Autodesk Fusion 360 part; units mm, degrees
(part 6 of 28)
  line L3353 (47.3065, 73.2735, -1.4859) -> (47.3065, 76.4735, -1.4859)
  line L3354 (47.3065, 76.4735, -1.4859) -> (49.3065, 76.4735, -1.4859)
  line L3355 (49.3065, 76.4735, -1.4859) -> (49.3065, 73.2735, -1.4859)
  line L3356 (84.2315, 73.2735, -1.4859) -> (82.2315, 73.2735, -1.4859)
  line L3357 (82.2315, 73.2735, -1.4859) -> (82.2315, 76.4735, -1.4859)
  line L3358 (82.2315, 76.4735, -1.4859) -> (84.2315, 76.4735, -1.4859)
  line L3359 (84.2315, 76.4735, -1.4859) -> (84.2315, 73.2735, -1.4859)
  line L3360 (119.1565, 73.2735, -1.4859) -> (117.1565, 73.2735, -1.4859)
  line L3361 (117.1565, 73.2735, -1.4859) -> (117.1565, 76.4735, -1.4859)
  line L3362 (117.1565, 76.4735, -1.4859) -> (119.1565, 76.4735, -1.4859)
  line L3363 (119.1565, 76.4735, -1.4859) -> (119.1565, 73.2735, -1.4859)
  line L3364 (19.1718, 76.4304, -1.4859) -> (19.3529, 76.3554, -1.4859)
  line L3365 (19.3529, 76.3554, -1.4859) -> (19.5159, 76.2465, -1.4859)
  line L3366 (19.5159, 76.2465, -1.4859) -> (19.6545, 76.1079, -1.4859)
  line L3367 (19.6545, 76.1079, -1.4859) -> (19.7634, 75.9449, -1.4859)
  line L3368 (19.7634, 75.9449, -1.4859) -> (19.8385, 75.7638, -1.4859)
  line L3369 (19.8385, 75.7638, -1.4859) -> (19.8767, 75.5715, -1.4859)
  line L3370 (19.8767, 75.5715, -1.4859) -> (19.8815, 75.4735, -1.4859)
  line L3371 (19.8815, 75.4735, -1.4859) -> (19.8815, 74.2735, -1.4859)
  line L3372 (19.8815, 74.2735, -1.4859) -> (19.8767, 74.1755, -1.4859)
  line L3373 (19.8767, 74.1755, -1.4859) -> (19.8385, 73.9832, -1.4859)
  line L3374 (19.8385, 73.9832, -1.4859) -> (19.7634, 73.8021, -1.4859)
  line L3375 (19.7634, 73.8021, -1.4859) -> (19.6545, 73.6391, -1.4859)
  line L3376 (19.6545, 73.6391, -1.4859) -> (19.5159, 73.5005, -1.4859)
  line L3377 (19.5159, 73.5005, -1.4859) -> (19.3529, 73.3916, -1.4859)
  line L3378 (19.3529, 73.3916, -1.4859) -> (19.1718, 73.3165, -1.4859)
  line L3379 (19.1718, 73.3165, -1.4859) -> (18.9795, 73.2783, -1.4859)
  line L3380 (18.9795, 73.2783, -1.4859) -> (18.7835, 73.2783, -1.4859)
  line L3381 (18.7835, 73.2783, -1.4859) -> (18.5912, 73.3165, -1.4859)
  line L3382 (18.5912, 73.3165, -1.4859) -> (18.4101, 73.3916, -1.4859)
  line L3383 (18.4101, 73.3916, -1.4859) -> (18.2471, 73.5005, -1.4859)
  line L3384 (18.2471, 73.5005, -1.4859) -> (18.1085, 73.6391, -1.4859)
  line L3385 (18.1085, 73.6391, -1.4859) -> (17.9996, 73.8021, -1.4859)
  line L3386 (17.9996, 73.8021, -1.4859) -> (17.9246, 73.9832, -1.4859)
  line L3387 (17.9246, 73.9832, -1.4859) -> (17.8863, 74.1755, -1.4859)
  line L3388 (17.8863, 74.1755, -1.4859) -> (17.8815, 74.2735, -1.4859)
  line L3389 (17.8815, 74.2735, -1.4859) -> (17.8815, 75.4735, -1.4859)
  line L3390 (17.8815, 75.4735, -1.4859) -> (17.8863, 75.5715, -1.4859)
  line L3391 (17.8863, 75.5715, -1.4859) -> (17.9246, 75.7638, -1.4859)
  line L3392 (17.9246, 75.7638, -1.4859) -> (17.9996, 75.9449, -1.4859)
  line L3393 (17.9996, 75.9449, -1.4859) -> (18.1085, 76.1079, -1.4859)
  line L3394 (18.1085, 76.1079, -1.4859) -> (18.2471, 76.2465, -1.4859)
  line L3395 (18.2471, 76.2465, -1.4859) -> (18.4101, 76.3554, -1.4859)
  line L3396 (18.4101, 76.3554, -1.4859) -> (18.5912, 76.4304, -1.4859)
  line L3397 (18.5912, 76.4304, -1.4859) -> (18.7835, 76.4687, -1.4859)
  line L3398 (18.7835, 76.4687, -1.4859) -> (18.9795, 76.4687, -1.4859)
  line L3399 (18.9795, 76.4687, -1.4859) -> (19.1718, 76.4304, -1.4859)
  line L3400 (54.0968, 76.4304, -1.4859) -> (54.2779, 76.3554, -1.4859)
  line L3401 (54.2779, 76.3554, -1.4859) -> (54.4409, 76.2465, -1.4859)
  line L3402 (54.4409, 76.2465, -1.4859) -> (54.5795, 76.1079, -1.4859)
  line L3403 (54.5795, 76.1079, -1.4859) -> (54.6884, 75.9449, -1.4859)
  line L3404 (54.6884, 75.9449, -1.4859) -> (54.7635, 75.7638, -1.4859)
  line L3405 (54.7635, 75.7638, -1.4859) -> (54.8017, 75.5715, -1.4859)
  line L3406 (54.8017, 75.5715, -1.4859) -> (54.8065, 75.4735, -1.4859)
  line L3407 (54.8065, 75.4735, -1.4859) -> (54.8065, 74.2735, -1.4859)
  line L3408 (54.8065, 74.2735, -1.4859) -> (54.8017, 74.1755, -1.4859)
  line L3409 (54.8017, 74.1755, -1.4859) -> (54.7635, 73.9832, -1.4859)
  line L3410 (54.7635, 73.9832, -1.4859) -> (54.6884, 73.8021, -1.4859)
  line L3411 (54.6884, 73.8021, -1.4859) -> (54.5795, 73.6391, -1.4859)
  line L3412 (54.5795, 73.6391, -1.4859) -> (54.4409, 73.5005, -1.4859)
  line L3413 (54.4409, 73.5005, -1.4859) -> (54.2779, 73.3916, -1.4859)
  line L3414 (54.2779, 73.3916, -1.4859) -> (54.0968, 73.3165, -1.4859)
  line L3415 (54.0968, 73.3165, -1.4859) -> (53.9045, 73.2783, -1.4859)
  line L3416 (53.9045, 73.2783, -1.4859) -> (53.7085, 73.2783, -1.4859)
  line L3417 (53.7085, 73.2783, -1.4859) -> (53.5162, 73.3165, -1.4859)
  line L3418 (53.5162, 73.3165, -1.4859) -> (53.3351, 73.3916, -1.4859)
  line L3419 (53.3351, 73.3916, -1.4859) -> (53.1721, 73.5005, -1.4859)
  line L3420 (53.1721, 73.5005, -1.4859) -> (53.0335, 73.6391, -1.4859)
  line L3421 (53.0335, 73.6391, -1.4859) -> (52.9246, 73.8021, -1.4859)
  line L3422 (52.9246, 73.8021, -1.4859) -> (52.8496, 73.9832, -1.4859)
  line L3423 (52.8496, 73.9832, -1.4859) -> (52.8113, 74.1755, -1.4859)
  line L3424 (52.8113, 74.1755, -1.4859) -> (52.8065, 74.2735, -1.4859)
  line L3425 (52.8065, 74.2735, -1.4859) -> (52.8065, 75.4735, -1.4859)
  line L3426 (52.8065, 75.4735, -1.4859) -> (52.8113, 75.5715, -1.4859)
  line L3427 (52.8113, 75.5715, -1.4859) -> (52.8496, 75.7638, -1.4859)
  line L3428 (52.8496, 75.7638, -1.4859) -> (52.9246, 75.9449, -1.4859)
  line L3429 (52.9246, 75.9449, -1.4859) -> (53.0335, 76.1079, -1.4859)
  line L3430 (53.0335, 76.1079, -1.4859) -> (53.1721, 76.2465, -1.4859)
  line L3431 (53.1721, 76.2465, -1.4859) -> (53.3351, 76.3554, -1.4859)
  line L3432 (53.3351, 76.3554, -1.4859) -> (53.5162, 76.4304, -1.4859)
  line L3433 (53.5162, 76.4304, -1.4859) -> (53.7085, 76.4687, -1.4859)
  line L3434 (53.7085, 76.4687, -1.4859) -> (53.9045, 76.4687, -1.4859)
  line L3435 (53.9045, 76.4687, -1.4859) -> (54.0968, 76.4304, -1.4859)
  line L3436 (89.0218, 76.4304, -1.4859) -> (89.2029, 76.3554, -1.4859)
  line L3437 (89.2029, 76.3554, -1.4859) -> (89.3659, 76.2465, -1.4859)
  line L3438 (89.3659, 76.2465, -1.4859) -> (89.5045, 76.1079, -1.4859)
  line L3439 (89.5045, 76.1079, -1.4859) -> (89.6134, 75.9449, -1.4859)
  line L3440 (89.6134, 75.9449, -1.4859) -> (89.6885, 75.7638, -1.4859)
  line L3441 (89.6885, 75.7638, -1.4859) -> (89.7267, 75.5715, -1.4859)
  line L3442 (89.7267, 75.5715, -1.4859) -> (89.7315, 75.4735, -1.4859)
  line L3443 (89.7315, 75.4735, -1.4859) -> (89.7315, 74.2735, -1.4859)
  line L3444 (89.7315, 74.2735, -1.4859) -> (89.7267, 74.1755, -1.4859)
  line L3445 (89.7267, 74.1755, -1.4859) -> (89.6885, 73.9832, -1.4859)
  line L3446 (89.6885, 73.9832, -1.4859) -> (89.6134, 73.8021, -1.4859)
  line L3447 (89.6134, 73.8021, -1.4859) -> (89.5045, 73.6391, -1.4859)
  line L3448 (89.5045, 73.6391, -1.4859) -> (89.3659, 73.5005, -1.4859)
  line L3449 (89.3659, 73.5005, -1.4859) -> (89.2029, 73.3916, -1.4859)
  line L3450 (89.2029, 73.3916, -1.4859) -> (89.0218, 73.3165, -1.4859)
  line L3451 (89.0218, 73.3165, -1.4859) -> (88.8295, 73.2783, -1.4859)
  line L3452 (88.8295, 73.2783, -1.4859) -> (88.6335, 73.2783, -1.4859)
  line L3453 (88.6335, 73.2783, -1.4859) -> (88.4412, 73.3165, -1.4859)
  line L3454 (88.4412, 73.3165, -1.4859) -> (88.2601, 73.3916, -1.4859)
  line L3455 (88.2601, 73.3916, -1.4859) -> (88.0971, 73.5005, -1.4859)
  line L3456 (88.0971, 73.5005, -1.4859) -> (87.9585, 73.6391, -1.4859)
  line L3457 (87.9585, 73.6391, -1.4859) -> (87.8496, 73.8021, -1.4859)
  line L3458 (87.8496, 73.8021, -1.4859) -> (87.7746, 73.9832, -1.4859)
  line L3459 (87.7746, 73.9832, -1.4859) -> (87.7363, 74.1755, -1.4859)
  line L3460 (87.7363, 74.1755, -1.4859) -> (87.7315, 74.2735, -1.4859)
  line L3461 (87.7315, 74.2735, -1.4859) -> (87.7315, 75.4735, -1.4859)
  line L3462 (87.7315, 75.4735, -1.4859) -> (87.7363, 75.5715, -1.4859)
  line L3463 (87.7363, 75.5715, -1.4859) -> (87.7746, 75.7638, -1.4859)
  line L3464 (87.7746, 75.7638, -1.4859) -> (87.8496, 75.9449, -1.4859)
  line L3465 (87.8496, 75.9449, -1.4859) -> (87.9585, 76.1079, -1.4859)
  line L3466 (87.9585, 76.1079, -1.4859) -> (88.0971, 76.2465, -1.4859)
  line L3467 (88.0971, 76.2465, -1.4859) -> (88.2601, 76.3554, -1.4859)
  line L3468 (88.2601, 76.3554, -1.4859) -> (88.4412, 76.4304, -1.4859)
  line L3469 (88.4412, 76.4304, -1.4859) -> (88.6335, 76.4687, -1.4859)
  line L3470 (88.6335, 76.4687, -1.4859) -> (88.8295, 76.4687, -1.4859)
  line L3471 (88.8295, 76.4687, -1.4859) -> (89.0218, 76.4304, -1.4859)
  line L3472 (123.9468, 76.4304, -1.4859) -> (124.1279, 76.3554, -1.4859)
  line L3473 (124.1279, 76.3554, -1.4859) -> (124.2909, 76.2465, -1.4859)
  line L3474 (124.2909, 76.2465, -1.4859) -> (124.4295, 76.1079, -1.4859)
  line L3475 (124.4295, 76.1079, -1.4859) -> (124.5384, 75.9449, -1.4859)
  line L3476 (124.5384, 75.9449, -1.4859) -> (124.6135, 75.7638, -1.4859)
  line L3477 (124.6135, 75.7638, -1.4859) -> (124.6517, 75.5715, -1.4859)
  line L3478 (124.6517, 75.5715, -1.4859) -> (124.6565, 75.4735, -1.4859)
  line L3479 (124.6565, 75.4735, -1.4859) -> (124.6565, 74.2735, -1.4859)
  line L3480 (124.6565, 74.2735, -1.4859) -> (124.6517, 74.1755, -1.4859)
  line L3481 (124.6517, 74.1755, -1.4859) -> (124.6135, 73.9832, -1.4859)
  line L3482 (124.6135, 73.9832, -1.4859) -> (124.5384, 73.8021, -1.4859)
  line L3483 (124.5384, 73.8021, -1.4859) -> (124.4295, 73.6391, -1.4859)
  line L3484 (124.4295, 73.6391, -1.4859) -> (124.2909, 73.5005, -1.4859)
  line L3485 (124.2909, 73.5005, -1.4859) -> (124.1279, 73.3916, -1.4859)
  line L3486 (124.1279, 73.3916, -1.4859) -> (123.9468, 73.3165, -1.4859)
  line L3487 (123.9468, 73.3165, -1.4859) -> (123.7545, 73.2783, -1.4859)
  line L3488 (123.7545, 73.2783, -1.4859) -> (123.5585, 73.2783, -1.4859)
  line L3489 (123.5585, 73.2783, -1.4859) -> (123.3662, 73.3165, -1.4859)
  line L3490 (123.3662, 73.3165, -1.4859) -> (123.1851, 73.3916, -1.4859)
  line L3491 (123.1851, 73.3916, -1.4859) -> (123.0221, 73.5005, -1.4859)
  line L3492 (123.0221, 73.5005, -1.4859) -> (122.8835, 73.6391, -1.4859)
  line L3493 (122.8835, 73.6391, -1.4859) -> (122.7746, 73.8021, -1.4859)
  line L3494 (122.7746, 73.8021, -1.4859) -> (122.6996, 73.9832, -1.4859)
  line L3495 (122.6996, 73.9832, -1.4859) -> (122.6613, 74.1755, -1.4859)
  line L3496 (122.6613, 74.1755, -1.4859) -> (122.6565, 74.2735, -1.4859)
  line L3497 (122.6565, 74.2735, -1.4859) -> (122.6565, 75.4735, -1.4859)
  line L3498 (122.6565, 75.4735, -1.4859) -> (122.6613, 75.5715, -1.4859)
  line L3499 (122.6613, 75.5715, -1.4859) -> (122.6996, 75.7638, -1.4859)
  line L3500 (122.6996, 75.7638, -1.4859) -> (122.7746, 75.9449, -1.4859)
  line L3501 (122.7746, 75.9449, -1.4859) -> (122.8835, 76.1079, -1.4859)
  line L3502 (122.8835, 76.1079, -1.4859) -> (123.0221, 76.2465, -1.4859)
  line L3503 (123.0221, 76.2465, -1.4859) -> (123.1851, 76.3554, -1.4859)
  line L3504 (123.1851, 76.3554, -1.4859) -> (123.3662, 76.4304, -1.4859)
  line L3505 (123.3662, 76.4304, -1.4859) -> (123.5585, 76.4687, -1.4859)
  line L3506 (123.5585, 76.4687, -1.4859) -> (123.7545, 76.4687, -1.4859)
  line L3507 (123.7545, 76.4687, -1.4859) -> (123.9468, 76.4304, -1.4859)
  line L3508 (14.4673, 82.8132, -1.4859) -> (14.661, 82.7825, -1.4859)
  line L3509 (14.661, 82.7825, -1.4859) -> (14.8475, 82.7219, -1.4859)
  line L3510 (14.8475, 82.7219, -1.4859) -> (15.0223, 82.6328, -1.4859)
  line L3511 (15.0223, 82.6328, -1.4859) -> (15.181, 82.5175, -1.4859)
  line L3512 (15.181, 82.5175, -1.4859) -> (15.3197, 82.3788, -1.4859)
  line L3513 (15.3197, 82.3788, -1.4859) -> (15.435, 82.2202, -1.4859)
  line L3514 (15.435, 82.2202, -1.4859) -> (15.524, 82.0454, -1.4859)
  line L3515 (15.524, 82.0454, -1.4859) -> (15.5846, 81.8588, -1.4859)
  line L3516 (15.5846, 81.8588, -1.4859) -> (15.6153, 81.6651, -1.4859)
  line L3517 (15.6153, 81.6651, -1.4859) -> (15.6153, 81.469, -1.4859)
  line L3518 (15.6153, 81.469, -1.4859) -> (15.5846, 81.2752, -1.4859)
  line L3519 (15.5846, 81.2752, -1.4859) -> (15.524, 81.0887, -1.4859)
  line L3520 (15.524, 81.0887, -1.4859) -> (15.435, 80.9139, -1.4859)
  line L3521 (15.435, 80.9139, -1.4859) -> (15.3197, 80.7552, -1.4859)
  line L3522 (15.3197, 80.7552, -1.4859) -> (15.181, 80.6165, -1.4859)
  line L3523 (15.181, 80.6165, -1.4859) -> (15.0223, 80.5012, -1.4859)
  line L3524 (15.0223, 80.5012, -1.4859) -> (14.8475, 80.4122, -1.4859)
  line L3525 (14.8475, 80.4122, -1.4859) -> (14.661, 80.3516, -1.4859)
  line L3526 (14.661, 80.3516, -1.4859) -> (14.4673, 80.3209, -1.4859)
  line L3527 (14.4673, 80.3209, -1.4859) -> (14.3692, 80.317, -1.4859)
  line L3528 (14.3692, 80.317, -1.4859) -> (13.8692, 80.317, -1.4859)
  line L3529 (13.8692, 80.317, -1.4859) -> (13.7711, 80.3209, -1.4859)
  line L3530 (13.7711, 80.3209, -1.4859) -> (13.5774, 80.3516, -1.4859)
  line L3531 (13.5774, 80.3516, -1.4859) -> (13.3908, 80.4122, -1.4859)
  line L3532 (13.3908, 80.4122, -1.4859) -> (13.2161, 80.5012, -1.4859)
  line L3533 (13.2161, 80.5012, -1.4859) -> (13.0574, 80.6165, -1.4859)
  line L3534 (13.0574, 80.6165, -1.4859) -> (12.9187, 80.7552, -1.4859)
  line L3535 (12.9187, 80.7552, -1.4859) -> (12.8034, 80.9139, -1.4859)
  line L3536 (12.8034, 80.9139, -1.4859) -> (12.7143, 81.0887, -1.4859)
  line L3537 (12.7143, 81.0887, -1.4859) -> (12.6537, 81.2752, -1.4859)
  line L3538 (12.6537, 81.2752, -1.4859) -> (12.623, 81.469, -1.4859)
  line L3539 (12.623, 81.469, -1.4859) -> (12.623, 81.6651, -1.4859)
  line L3540 (12.623, 81.6651, -1.4859) -> (12.6537, 81.8588, -1.4859)
  line L3541 (12.6537, 81.8588, -1.4859) -> (12.7143, 82.0454, -1.4859)
  line L3542 (12.7143, 82.0454, -1.4859) -> (12.8034, 82.2202, -1.4859)
  line L3543 (12.8034, 82.2202, -1.4859) -> (12.9187, 82.3788, -1.4859)
  line L3544 (12.9187, 82.3788, -1.4859) -> (13.0574, 82.5175, -1.4859)
  line L3545 (13.0574, 82.5175, -1.4859) -> (13.2161, 82.6328, -1.4859)
  line L3546 (13.2161, 82.6328, -1.4859) -> (13.3908, 82.7219, -1.4859)
  line L3547 (13.3908, 82.7219, -1.4859) -> (13.5774, 82.7825, -1.4859)
  line L3548 (13.5774, 82.7825, -1.4859) -> (13.7711, 82.8132, -1.4859)
  line L3549 (13.7711, 82.8132, -1.4859) -> (13.8692, 82.817, -1.4859)
  line L3550 (13.8692, 82.817, -1.4859) -> (14.3692, 82.817, -1.4859)
  line L3551 (14.3692, 82.817, -1.4859) -> (14.4673, 82.8132, -1.4859)
  line L3552 (22.0873, 82.8132, -1.4859) -> (22.281, 82.7825, -1.4859)
  line L3553 (22.281, 82.7825, -1.4859) -> (22.4675, 82.7219, -1.4859)
  line L3554 (22.4675, 82.7219, -1.4859) -> (22.6423, 82.6328, -1.4859)
  line L3555 (22.6423, 82.6328, -1.4859) -> (22.801, 82.5175, -1.4859)
  line L3556 (22.801, 82.5175, -1.4859) -> (22.9397, 82.3788, -1.4859)
  line L3557 (22.9397, 82.3788, -1.4859) -> (23.055, 82.2202, -1.4859)
  line L3558 (23.055, 82.2202, -1.4859) -> (23.144, 82.0454, -1.4859)
  line L3559 (23.144, 82.0454, -1.4859) -> (23.2046, 81.8588, -1.4859)
  line L3560 (23.2046, 81.8588, -1.4859) -> (23.2353, 81.6651, -1.4859)
  line L3561 (23.2353, 81.6651, -1.4859) -> (23.2353, 81.469, -1.4859)
  line L3562 (23.2353, 81.469, -1.4859) -> (23.2046, 81.2752, -1.4859)
  line L3563 (23.2046, 81.2752, -1.4859) -> (23.144, 81.0887, -1.4859)
  line L3564 (23.144, 81.0887, -1.4859) -> (23.055, 80.9139, -1.4859)
  line L3565 (23.055, 80.9139, -1.4859) -> (22.9397, 80.7552, -1.4859)
  line L3566 (22.9397, 80.7552, -1.4859) -> (22.801, 80.6165, -1.4859)
  line L3567 (22.801, 80.6165, -1.4859) -> (22.6423, 80.5012, -1.4859)
  line L3568 (22.6423, 80.5012, -1.4859) -> (22.4675, 80.4122, -1.4859)
  line L3569 (22.4675, 80.4122, -1.4859) -> (22.281, 80.3516, -1.4859)
  line L3570 (22.281, 80.3516, -1.4859) -> (22.0873, 80.3209, -1.4859)
  line L3571 (22.0873, 80.3209, -1.4859) -> (21.9892, 80.317, -1.4859)
  line L3572 (21.9892, 80.317, -1.4859) -> (21.4892, 80.317, -1.4859)
  line L3573 (21.4892, 80.317, -1.4859) -> (21.3911, 80.3209, -1.4859)
  line L3574 (21.3911, 80.3209, -1.4859) -> (21.1974, 80.3516, -1.4859)
  line L3575 (21.1974, 80.3516, -1.4859) -> (21.0108, 80.4122, -1.4859)
  line L3576 (21.0108, 80.4122, -1.4859) -> (20.8361, 80.5012, -1.4859)
  line L3577 (20.8361, 80.5012, -1.4859) -> (20.6774, 80.6165, -1.4859)
  line L3578 (20.6774, 80.6165, -1.4859) -> (20.5387, 80.7552, -1.4859)
  line L3579 (20.5387, 80.7552, -1.4859) -> (20.4234, 80.9139, -1.4859)
  line L3580 (20.4234, 80.9139, -1.4859) -> (20.3343, 81.0887, -1.4859)
  line L3581 (20.3343, 81.0887, -1.4859) -> (20.2737, 81.2752, -1.4859)
  line L3582 (20.2737, 81.2752, -1.4859) -> (20.243, 81.469, -1.4859)
  line L3583 (20.243, 81.469, -1.4859) -> (20.243, 81.6651, -1.4859)
  line L3584 (20.243, 81.6651, -1.4859) -> (20.2737, 81.8588, -1.4859)
  line L3585 (20.2737, 81.8588, -1.4859) -> (20.3343, 82.0454, -1.4859)
  line L3586 (20.3343, 82.0454, -1.4859) -> (20.4234, 82.2202, -1.4859)
  line L3587 (20.4234, 82.2202, -1.4859) -> (20.5387, 82.3788, -1.4859)
  line L3588 (20.5387, 82.3788, -1.4859) -> (20.6774, 82.5175, -1.4859)
  line L3589 (20.6774, 82.5175, -1.4859) -> (20.8361, 82.6328, -1.4859)
  line L3590 (20.8361, 82.6328, -1.4859) -> (21.0108, 82.7219, -1.4859)
  line L3591 (21.0108, 82.7219, -1.4859) -> (21.1974, 82.7825, -1.4859)
  line L3592 (21.1974, 82.7825, -1.4859) -> (21.3911, 82.8132, -1.4859)
  line L3593 (21.3911, 82.8132, -1.4859) -> (21.4892, 82.817, -1.4859)
  line L3594 (21.4892, 82.817, -1.4859) -> (21.9892, 82.817, -1.4859)
  line L3595 (21.9892, 82.817, -1.4859) -> (22.0873, 82.8132, -1.4859)
  line L3596 (49.3923, 82.8132, -1.4859) -> (49.586, 82.7825, -1.4859)
  line L3597 (49.586, 82.7825, -1.4859) -> (49.7725, 82.7219, -1.4859)
  line L3598 (49.7725, 82.7219, -1.4859) -> (49.9473, 82.6328, -1.4859)
  line L3599 (49.9473, 82.6328, -1.4859) -> (50.106, 82.5175, -1.4859)
  line L3600 (50.106, 82.5175, -1.4859) -> (50.2447, 82.3788, -1.4859)
  line L3601 (50.2447, 82.3788, -1.4859) -> (50.36, 82.2202, -1.4859)
  line L3602 (50.36, 82.2202, -1.4859) -> (50.449, 82.0454, -1.4859)
  line L3603 (50.449, 82.0454, -1.4859) -> (50.5096, 81.8588, -1.4859)
  line L3604 (50.5096, 81.8588, -1.4859) -> (50.5403, 81.6651, -1.4859)
  line L3605 (50.5403, 81.6651, -1.4859) -> (50.5403, 81.469, -1.4859)
  line L3606 (50.5403, 81.469, -1.4859) -> (50.5096, 81.2752, -1.4859)
  line L3607 (50.5096, 81.2752, -1.4859) -> (50.449, 81.0887, -1.4859)
  line L3608 (50.449, 81.0887, -1.4859) -> (50.36, 80.9139, -1.4859)
  line L3609 (50.36, 80.9139, -1.4859) -> (50.2447, 80.7552, -1.4859)
  line L3610 (50.2447, 80.7552, -1.4859) -> (50.106, 80.6165, -1.4859)
  line L3611 (50.106, 80.6165, -1.4859) -> (49.9473, 80.5012, -1.4859)
  line L3612 (49.9473, 80.5012, -1.4859) -> (49.7725, 80.4122, -1.4859)
  line L3613 (49.7725, 80.4122, -1.4859) -> (49.586, 80.3516, -1.4859)
  line L3614 (49.586, 80.3516, -1.4859) -> (49.3923, 80.3209, -1.4859)
  line L3615 (49.3923, 80.3209, -1.4859) -> (49.2942, 80.317, -1.4859)
  line L3616 (49.2942, 80.317, -1.4859) -> (48.7942, 80.317, -1.4859)
  line L3617 (48.7942, 80.317, -1.4859) -> (48.6961, 80.3209, -1.4859)
  line L3618 (48.6961, 80.3209, -1.4859) -> (48.5024, 80.3516, -1.4859)
  line L3619 (48.5024, 80.3516, -1.4859) -> (48.3158, 80.4122, -1.4859)
  line L3620 (48.3158, 80.4122, -1.4859) -> (48.1411, 80.5012, -1.4859)
  line L3621 (48.1411, 80.5012, -1.4859) -> (47.9824, 80.6165, -1.4859)
  line L3622 (47.9824, 80.6165, -1.4859) -> (47.8437, 80.7552, -1.4859)
  line L3623 (47.8437, 80.7552, -1.4859) -> (47.7284, 80.9139, -1.4859)
  line L3624 (47.7284, 80.9139, -1.4859) -> (47.6393, 81.0887, -1.4859)
  line L3625 (47.6393, 81.0887, -1.4859) -> (47.5787, 81.2752, -1.4859)
  line L3626 (47.5787, 81.2752, -1.4859) -> (47.548, 81.469, -1.4859)
  line L3627 (47.548, 81.469, -1.4859) -> (47.548, 81.6651, -1.4859)
  line L3628 (47.548, 81.6651, -1.4859) -> (47.5787, 81.8588, -1.4859)
  line L3629 (47.5787, 81.8588, -1.4859) -> (47.6393, 82.0454, -1.4859)
  line L3630 (47.6393, 82.0454, -1.4859) -> (47.7284, 82.2202, -1.4859)
  line L3631 (47.7284, 82.2202, -1.4859) -> (47.8437, 82.3788, -1.4859)
  line L3632 (47.8437, 82.3788, -1.4859) -> (47.9824, 82.5175, -1.4859)
  line L3633 (47.9824, 82.5175, -1.4859) -> (48.1411, 82.6328, -1.4859)
  line L3634 (48.1411, 82.6328, -1.4859) -> (48.3158, 82.7219, -1.4859)
  line L3635 (48.3158, 82.7219, -1.4859) -> (48.5024, 82.7825, -1.4859)
  line L3636 (48.5024, 82.7825, -1.4859) -> (48.6961, 82.8132, -1.4859)
  line L3637 (48.6961, 82.8132, -1.4859) -> (48.7942, 82.817, -1.4859)
  line L3638 (48.7942, 82.817, -1.4859) -> (49.2942, 82.817, -1.4859)
  line L3639 (49.2942, 82.817, -1.4859) -> (49.3923, 82.8132, -1.4859)
  line L3640 (57.0123, 82.8132, -1.4859) -> (57.206, 82.7825, -1.4859)
  line L3641 (57.206, 82.7825, -1.4859) -> (57.3925, 82.7219, -1.4859)
  line L3642 (57.3925, 82.7219, -1.4859) -> (57.5673, 82.6328, -1.4859)
  line L3643 (57.5673, 82.6328, -1.4859) -> (57.726, 82.5175, -1.4859)
  line L3644 (57.726, 82.5175, -1.4859) -> (57.8647, 82.3788, -1.4859)
  line L3645 (57.8647, 82.3788, -1.4859) -> (57.98, 82.2202, -1.4859)
  line L3646 (57.98, 82.2202, -1.4859) -> (58.069, 82.0454, -1.4859)
  line L3647 (58.069, 82.0454, -1.4859) -> (58.1296, 81.8588, -1.4859)
  line L3648 (58.1296, 81.8588, -1.4859) -> (58.1603, 81.6651, -1.4859)
  line L3649 (58.1603, 81.6651, -1.4859) -> (58.1603, 81.469, -1.4859)
  line L3650 (58.1603, 81.469, -1.4859) -> (58.1296, 81.2752, -1.4859)
  line L3651 (58.1296, 81.2752, -1.4859) -> (58.069, 81.0887, -1.4859)
  line L3652 (58.069, 81.0887, -1.4859) -> (57.98, 80.9139, -1.4859)
  line L3653 (57.98, 80.9139, -1.4859) -> (57.8647, 80.7552, -1.4859)
  line L3654 (57.8647, 80.7552, -1.4859) -> (57.726, 80.6165, -1.4859)
  line L3655 (57.726, 80.6165, -1.4859) -> (57.5673, 80.5012, -1.4859)
  line L3656 (57.5673, 80.5012, -1.4859) -> (57.3925, 80.4122, -1.4859)
  line L3657 (57.3925, 80.4122, -1.4859) -> (57.206, 80.3516, -1.4859)
  line L3658 (57.206, 80.3516, -1.4859) -> (57.0123, 80.3209, -1.4859)
  line L3659 (57.0123, 80.3209, -1.4859) -> (56.9142, 80.317, -1.4859)
  line L3660 (56.9142, 80.317, -1.4859) -> (56.4142, 80.317, -1.4859)
  line L3661 (56.4142, 80.317, -1.4859) -> (56.3161, 80.3209, -1.4859)
  line L3662 (56.3161, 80.3209, -1.4859) -> (56.1224, 80.3516, -1.4859)
  line L3663 (56.1224, 80.3516, -1.4859) -> (55.9358, 80.4122, -1.4859)
  line L3664 (55.9358, 80.4122, -1.4859) -> (55.7611, 80.5012, -1.4859)
  line L3665 (55.7611, 80.5012, -1.4859) -> (55.6024, 80.6165, -1.4859)
  line L3666 (55.6024, 80.6165, -1.4859) -> (55.4637, 80.7552, -1.4859)
  line L3667 (55.4637, 80.7552, -1.4859) -> (55.3484, 80.9139, -1.4859)
  line L3668 (55.3484, 80.9139, -1.4859) -> (55.2593, 81.0887, -1.4859)
  line L3669 (55.2593, 81.0887, -1.4859) -> (55.1987, 81.2752, -1.4859)
  line L3670 (55.1987, 81.2752, -1.4859) -> (55.168, 81.469, -1.4859)
  line L3671 (55.168, 81.469, -1.4859) -> (55.168, 81.6651, -1.4859)
  line L3672 (55.168, 81.6651, -1.4859) -> (55.1987, 81.8588, -1.4859)
  line L3673 (55.1987, 81.8588, -1.4859) -> (55.2593, 82.0454, -1.4859)
  line L3674 (55.2593, 82.0454, -1.4859) -> (55.3484, 82.2202, -1.4859)
  line L3675 (55.3484, 82.2202, -1.4859) -> (55.4637, 82.3788, -1.4859)
  line L3676 (55.4637, 82.3788, -1.4859) -> (55.6024, 82.5175, -1.4859)
  line L3677 (55.6024, 82.5175, -1.4859) -> (55.7611, 82.6328, -1.4859)
  line L3678 (55.7611, 82.6328, -1.4859) -> (55.9358, 82.7219, -1.4859)
  line L3679 (55.9358, 82.7219, -1.4859) -> (56.1224, 82.7825, -1.4859)
  line L3680 (56.1224, 82.7825, -1.4859) -> (56.3161, 82.8132, -1.4859)
  line L3681 (56.3161, 82.8132, -1.4859) -> (56.4142, 82.817, -1.4859)
  line L3682 (56.4142, 82.817, -1.4859) -> (56.9142, 82.817, -1.4859)
  line L3683 (56.9142, 82.817, -1.4859) -> (57.0123, 82.8132, -1.4859)
  line L3684 (84.3173, 82.8132, -1.4859) -> (84.511, 82.7825, -1.4859)
  line L3685 (84.511, 82.7825, -1.4859) -> (84.6975, 82.7219, -1.4859)
  line L3686 (84.6975, 82.7219, -1.4859) -> (84.8723, 82.6328, -1.4859)
  line L3687 (84.8723, 82.6328, -1.4859) -> (85.031, 82.5175, -1.4859)
  line L3688 (85.031, 82.5175, -1.4859) -> (85.1697, 82.3788, -1.4859)
  line L3689 (85.1697, 82.3788, -1.4859) -> (85.285, 82.2202, -1.4859)
  line L3690 (85.285, 82.2202, -1.4859) -> (85.374, 82.0454, -1.4859)
  line L3691 (85.374, 82.0454, -1.4859) -> (85.4346, 81.8588, -1.4859)
  line L3692 (85.4346, 81.8588, -1.4859) -> (85.4653, 81.6651, -1.4859)
  line L3693 (85.4653, 81.6651, -1.4859) -> (85.4653, 81.469, -1.4859)
  line L3694 (85.4653, 81.469, -1.4859) -> (85.4346, 81.2752, -1.4859)
  line L3695 (85.4346, 81.2752, -1.4859) -> (85.374, 81.0887, -1.4859)
  line L3696 (85.374, 81.0887, -1.4859) -> (85.285, 80.9139, -1.4859)
  line L3697 (85.285, 80.9139, -1.4859) -> (85.1697, 80.7552, -1.4859)
  line L3698 (85.1697, 80.7552, -1.4859) -> (85.031, 80.6165, -1.4859)
  line L3699 (85.031, 80.6165, -1.4859) -> (84.8723, 80.5012, -1.4859)
  line L3700 (84.8723, 80.5012, -1.4859) -> (84.6975, 80.4122, -1.4859)
  line L3701 (84.6975, 80.4122, -1.4859) -> (84.511, 80.3516, -1.4859)
  line L3702 (84.511, 80.3516, -1.4859) -> (84.3173, 80.3209, -1.4859)
  line L3703 (84.3173, 80.3209, -1.4859) -> (84.2192, 80.317, -1.4859)
  line L3704 (84.2192, 80.317, -1.4859) -> (83.7192, 80.317, -1.4859)
  line L3705 (83.7192, 80.317, -1.4859) -> (83.6211, 80.3209, -1.4859)
  line L3706 (83.6211, 80.3209, -1.4859) -> (83.4274, 80.3516, -1.4859)
  line L3707 (83.4274, 80.3516, -1.4859) -> (83.2408, 80.4122, -1.4859)
  line L3708 (83.2408, 80.4122, -1.4859) -> (83.0661, 80.5012, -1.4859)
  line L3709 (83.0661, 80.5012, -1.4859) -> (82.9074, 80.6165, -1.4859)
  line L3710 (82.9074, 80.6165, -1.4859) -> (82.7687, 80.7552, -1.4859)
  line L3711 (82.7687, 80.7552, -1.4859) -> (82.6534, 80.9139, -1.4859)
  line L3712 (82.6534, 80.9139, -1.4859) -> (82.5643, 81.0887, -1.4859)
  line L3713 (82.5643, 81.0887, -1.4859) -> (82.5037, 81.2752, -1.4859)
  line L3714 (82.5037, 81.2752, -1.4859) -> (82.473, 81.469, -1.4859)
  line L3715 (82.473, 81.469, -1.4859) -> (82.473, 81.6651, -1.4859)
  line L3716 (82.473, 81.6651, -1.4859) -> (82.5037, 81.8588, -1.4859)
  line L3717 (82.5037, 81.8588, -1.4859) -> (82.5643, 82.0454, -1.4859)
  line L3718 (82.5643, 82.0454, -1.4859) -> (82.6534, 82.2202, -1.4859)
  line L3719 (82.6534, 82.2202, -1.4859) -> (82.7687, 82.3788, -1.4859)
  line L3720 (82.7687, 82.3788, -1.4859) -> (82.9074, 82.5175, -1.4859)
  line L3721 (82.9074, 82.5175, -1.4859) -> (83.0661, 82.6328, -1.4859)
  line L3722 (83.0661, 82.6328, -1.4859) -> (83.2408, 82.7219, -1.4859)
  line L3723 (83.2408, 82.7219, -1.4859) -> (83.4274, 82.7825, -1.4859)
  line L3724 (83.4274, 82.7825, -1.4859) -> (83.6211, 82.8132, -1.4859)
  line L3725 (83.6211, 82.8132, -1.4859) -> (83.7192, 82.817, -1.4859)
  line L3726 (83.7192, 82.817, -1.4859) -> (84.2192, 82.817, -1.4859)
  line L3727 (84.2192, 82.817, -1.4859) -> (84.3173, 82.8132, -1.4859)
  line L3728 (91.9373, 82.8132, -1.4859) -> (92.131, 82.7825, -1.4859)
  line L3729 (92.131, 82.7825, -1.4859) -> (92.3175, 82.7219, -1.4859)
  line L3730 (92.3175, 82.7219, -1.4859) -> (92.4923, 82.6328, -1.4859)
  line L3731 (92.4923, 82.6328, -1.4859) -> (92.651, 82.5175, -1.4859)
  line L3732 (92.651, 82.5175, -1.4859) -> (92.7897, 82.3788, -1.4859)
  line L3733 (92.7897, 82.3788, -1.4859) -> (92.905, 82.2202, -1.4859)
  line L3734 (92.905, 82.2202, -1.4859) -> (92.994, 82.0454, -1.4859)
  line L3735 (92.994, 82.0454, -1.4859) -> (93.0546, 81.8588, -1.4859)
  line L3736 (93.0546, 81.8588, -1.4859) -> (93.0853, 81.6651, -1.4859)
  line L3737 (93.0853, 81.6651, -1.4859) -> (93.0853, 81.469, -1.4859)
  line L3738 (93.0853, 81.469, -1.4859) -> (93.0546, 81.2752, -1.4859)
  line L3739 (93.0546, 81.2752, -1.4859) -> (92.994, 81.0887, -1.4859)
  line L3740 (92.994, 81.0887, -1.4859) -> (92.905, 80.9139, -1.4859)
  line L3741 (92.905, 80.9139, -1.4859) -> (92.7897, 80.7552, -1.4859)
  line L3742 (92.7897, 80.7552, -1.4859) -> (92.651, 80.6165, -1.4859)
  line L3743 (92.651, 80.6165, -1.4859) -> (92.4923, 80.5012, -1.4859)
  line L3744 (92.4923, 80.5012, -1.4859) -> (92.3175, 80.4122, -1.4859)
  line L3745 (92.3175, 80.4122, -1.4859) -> (92.131, 80.3516, -1.4859)
  line L3746 (92.131, 80.3516, -1.4859) -> (91.9373, 80.3209, -1.4859)
  line L3747 (91.9373, 80.3209, -1.4859) -> (91.8392, 80.317, -1.4859)
  line L3748 (91.8392, 80.317, -1.4859) -> (91.3392, 80.317, -1.4859)
  line L3749 (91.3392, 80.317, -1.4859) -> (91.2411, 80.3209, -1.4859)
  line L3750 (91.2411, 80.3209, -1.4859) -> (91.0474, 80.3516, -1.4859)
  line L3751 (91.0474, 80.3516, -1.4859) -> (90.8608, 80.4122, -1.4859)
  line L3752 (90.8608, 80.4122, -1.4859) -> (90.6861, 80.5012, -1.4859)
  line L3753 (90.6861, 80.5012, -1.4859) -> (90.5274, 80.6165, -1.4859)
  line L3754 (90.5274, 80.6165, -1.4859) -> (90.3887, 80.7552, -1.4859)
  line L3755 (90.3887, 80.7552, -1.4859) -> (90.2734, 80.9139, -1.4859)
  line L3756 (90.2734, 80.9139, -1.4859) -> (90.1843, 81.0887, -1.4859)
  line L3757 (90.1843, 81.0887, -1.4859) -> (90.1237, 81.2752, -1.4859)
  line L3758 (90.1237, 81.2752, -1.4859) -> (90.093, 81.469, -1.4859)
  line L3759 (90.093, 81.469, -1.4859) -> (90.093, 81.6651, -1.4859)
  line L3760 (90.093, 81.6651, -1.4859) -> (90.1237, 81.8588, -1.4859)
  line L3761 (90.1237, 81.8588, -1.4859) -> (90.1843, 82.0454, -1.4859)
  line L3762 (90.1843, 82.0454, -1.4859) -> (90.2734, 82.2202, -1.4859)
  line L3763 (90.2734, 82.2202, -1.4859) -> (90.3887, 82.3788, -1.4859)
  line L3764 (90.3887, 82.3788, -1.4859) -> (90.5274, 82.5175, -1.4859)
  line L3765 (90.5274, 82.5175, -1.4859) -> (90.6861, 82.6328, -1.4859)
  line L3766 (90.6861, 82.6328, -1.4859) -> (90.8608, 82.7219, -1.4859)
  line L3767 (90.8608, 82.7219, -1.4859) -> (91.0474, 82.7825, -1.4859)
  line L3768 (91.0474, 82.7825, -1.4859) -> (91.2411, 82.8132, -1.4859)
  line L3769 (91.2411, 82.8132, -1.4859) -> (91.3392, 82.817, -1.4859)
  line L3770 (91.3392, 82.817, -1.4859) -> (91.8392, 82.817, -1.4859)
  line L3771 (91.8392, 82.817, -1.4859) -> (91.9373, 82.8132, -1.4859)
  line L3772 (119.2423, 82.8132, -1.4859) -> (119.436, 82.7825, -1.4859)
  line L3773 (119.436, 82.7825, -1.4859) -> (119.6225, 82.7219, -1.4859)
  line L3774 (119.6225, 82.7219, -1.4859) -> (119.7973, 82.6328, -1.4859)
  line L3775 (119.7973, 82.6328, -1.4859) -> (119.956, 82.5175, -1.4859)
  line L3776 (119.956, 82.5175, -1.4859) -> (120.0947, 82.3788, -1.4859)
  line L3777 (120.0947, 82.3788, -1.4859) -> (120.21, 82.2202, -1.4859)
  line L3778 (120.21, 82.2202, -1.4859) -> (120.299, 82.0454, -1.4859)
  line L3779 (120.299, 82.0454, -1.4859) -> (120.3596, 81.8588, -1.4859)
  line L3780 (120.3596, 81.8588, -1.4859) -> (120.3903, 81.6651, -1.4859)
  line L3781 (120.3903, 81.6651, -1.4859) -> (120.3903, 81.469, -1.4859)
  line L3782 (120.3903, 81.469, -1.4859) -> (120.3596, 81.2752, -1.4859)
  line L3783 (120.3596, 81.2752, -1.4859) -> (120.299, 81.0887, -1.4859)
  line L3784 (120.299, 81.0887, -1.4859) -> (120.21, 80.9139, -1.4859)
  line L3785 (120.21, 80.9139, -1.4859) -> (120.0947, 80.7552, -1.4859)
  line L3786 (120.0947, 80.7552, -1.4859) -> (119.956, 80.6165, -1.4859)
  line L3787 (119.956, 80.6165, -1.4859) -> (119.7973, 80.5012, -1.4859)
  line L3788 (119.7973, 80.5012, -1.4859) -> (119.6225, 80.4122, -1.4859)
  line L3789 (119.6225, 80.4122, -1.4859) -> (119.436, 80.3516, -1.4859)
  line L3790 (119.436, 80.3516, -1.4859) -> (119.2423, 80.3209, -1.4859)
  line L3791 (119.2423, 80.3209, -1.4859) -> (119.1442, 80.317, -1.4859)
  line L3792 (119.1442, 80.317, -1.4859) -> (118.6442, 80.317, -1.4859)
  line L3793 (118.6442, 80.317, -1.4859) -> (118.5461, 80.3209, -1.4859)
  line L3794 (118.5461, 80.3209, -1.4859) -> (118.3524, 80.3516, -1.4859)
  line L3795 (118.3524, 80.3516, -1.4859) -> (118.1658, 80.4122, -1.4859)
  line L3796 (118.1658, 80.4122, -1.4859) -> (117.9911, 80.5012, -1.4859)
  line L3797 (117.9911, 80.5012, -1.4859) -> (117.8324, 80.6165, -1.4859)
  line L3798 (117.8324, 80.6165, -1.4859) -> (117.6937, 80.7552, -1.4859)
  line L3799 (117.6937, 80.7552, -1.4859) -> (117.5784, 80.9139, -1.4859)
  line L3800 (117.5784, 80.9139, -1.4859) -> (117.4893, 81.0887, -1.4859)
  line L3801 (117.4893, 81.0887, -1.4859) -> (117.4287, 81.2752, -1.4859)
  line L3802 (117.4287, 81.2752, -1.4859) -> (117.398, 81.469, -1.4859)
  line L3803 (117.398, 81.469, -1.4859) -> (117.398, 81.6651, -1.4859)
  line L3804 (117.398, 81.6651, -1.4859) -> (117.4287, 81.8588, -1.4859)
  line L3805 (117.4287, 81.8588, -1.4859) -> (117.4893, 82.0454, -1.4859)
  line L3806 (117.4893, 82.0454, -1.4859) -> (117.5784, 82.2202, -1.4859)
  line L3807 (117.5784, 82.2202, -1.4859) -> (117.6937, 82.3788, -1.4859)
  line L3808 (117.6937, 82.3788, -1.4859) -> (117.8324, 82.5175, -1.4859)
  line L3809 (117.8324, 82.5175, -1.4859) -> (117.9911, 82.6328, -1.4859)
  line L3810 (117.9911, 82.6328, -1.4859) -> (118.1658, 82.7219, -1.4859)
  line L3811 (118.1658, 82.7219, -1.4859) -> (118.3524, 82.7825, -1.4859)
  line L3812 (118.3524, 82.7825, -1.4859) -> (118.5461, 82.8132, -1.4859)
  line L3813 (118.5461, 82.8132, -1.4859) -> (118.6442, 82.817, -1.4859)
  line L3814 (118.6442, 82.817, -1.4859) -> (119.1442, 82.817, -1.4859)
  line L3815 (119.1442, 82.817, -1.4859) -> (119.2423, 82.8132, -1.4859)
  line L3816 (126.8623, 82.8132, -1.4859) -> (127.056, 82.7825, -1.4859)
  line L3817 (127.056, 82.7825, -1.4859) -> (127.2425, 82.7219, -1.4859)
  line L3818 (127.2425, 82.7219, -1.4859) -> (127.4173, 82.6328, -1.4859)
  line L3819 (127.4173, 82.6328, -1.4859) -> (127.576, 82.5175, -1.4859)
  line L3820 (127.576, 82.5175, -1.4859) -> (127.7147, 82.3788, -1.4859)
  line L3821 (127.7147, 82.3788, -1.4859) -> (127.83, 82.2202, -1.4859)
  line L3822 (127.83, 82.2202, -1.4859) -> (127.919, 82.0454, -1.4859)
  line L3823 (127.919, 82.0454, -1.4859) -> (127.9796, 81.8588, -1.4859)
  line L3824 (127.9796, 81.8588, -1.4859) -> (128.0103, 81.6651, -1.4859)
  line L3825 (128.0103, 81.6651, -1.4859) -> (128.0103, 81.469, -1.4859)
  line L3826 (128.0103, 81.469, -1.4859) -> (127.9796, 81.2752, -1.4859)
  line L3827 (127.9796, 81.2752, -1.4859) -> (127.919, 81.0887, -1.4859)
  line L3828 (127.919, 81.0887, -1.4859) -> (127.83, 80.9139, -1.4859)
  line L3829 (127.83, 80.9139, -1.4859) -> (127.7147, 80.7552, -1.4859)
  line L3830 (127.7147, 80.7552, -1.4859) -> (127.576, 80.6165, -1.4859)
  line L3831 (127.576, 80.6165, -1.4859) -> (127.4173, 80.5012, -1.4859)
  line L3832 (127.4173, 80.5012, -1.4859) -> (127.2425, 80.4122, -1.4859)
  line L3833 (127.2425, 80.4122, -1.4859) -> (127.056, 80.3516, -1.4859)
  line L3834 (127.056, 80.3516, -1.4859) -> (126.8623, 80.3209, -1.4859)
  line L3835 (126.8623, 80.3209, -1.4859) -> (126.7642, 80.317, -1.4859)
  line L3836 (126.7642, 80.317, -1.4859) -> (126.2642, 80.317, -1.4859)
  line L3837 (126.2642, 80.317, -1.4859) -> (126.1661, 80.3209, -1.4859)
  line L3838 (126.1661, 80.3209, -1.4859) -> (125.9724, 80.3516, -1.4859)
  line L3839 (125.9724, 80.3516, -1.4859) -> (125.7858, 80.4122, -1.4859)
  line L3840 (125.7858, 80.4122, -1.4859) -> (125.6111, 80.5012, -1.4859)
  line L3841 (125.6111, 80.5012, -1.4859) -> (125.4524, 80.6165, -1.4859)
  line L3842 (125.4524, 80.6165, -1.4859) -> (125.3137, 80.7552, -1.4859)
  line L3843 (125.3137, 80.7552, -1.4859) -> (125.1984, 80.9139, -1.4859)
  line L3844 (125.1984, 80.9139, -1.4859) -> (125.1093, 81.0887, -1.4859)
  line L3845 (125.1093, 81.0887, -1.4859) -> (125.0487, 81.2752, -1.4859)
  line L3846 (125.0487, 81.2752, -1.4859) -> (125.018, 81.469, -1.4859)
  line L3847 (125.018, 81.469, -1.4859) -> (125.018, 81.6651, -1.4859)
  line L3848 (125.018, 81.6651, -1.4859) -> (125.0487, 81.8588, -1.4859)
  line L3849 (125.0487, 81.8588, -1.4859) -> (125.1093, 82.0454, -1.4859)
  line L3850 (125.1093, 82.0454, -1.4859) -> (125.1984, 82.2202, -1.4859)
  line L3851 (125.1984, 82.2202, -1.4859) -> (125.3137, 82.3788, -1.4859)
  line L3852 (125.3137, 82.3788, -1.4859) -> (125.4524, 82.5175, -1.4859)
  line L3853 (125.4524, 82.5175, -1.4859) -> (125.6111, 82.6328, -1.4859)
  line L3854 (125.6111, 82.6328, -1.4859) -> (125.7858, 82.7219, -1.4859)
  line L3855 (125.7858, 82.7219, -1.4859) -> (125.9724, 82.7825, -1.4859)
  line L3856 (125.9724, 82.7825, -1.4859) -> (126.1661, 82.8132, -1.4859)
  line L3857 (126.1661, 82.8132, -1.4859) -> (126.2642, 82.817, -1.4859)
  line L3858 (126.2642, 82.817, -1.4859) -> (126.7642, 82.817, -1.4859)
  line L3859 (126.7642, 82.817, -1.4859) -> (126.8623, 82.8132, -1.4859)
  line L3860 (33.8345, 85.878, -1.4859) -> (34.021, 85.8174, -1.4859)
  line L3861 (34.021, 85.8174, -1.4859) -> (34.1958, 85.7283, -1.4859)
  line L3862 (34.1958, 85.7283, -1.4859) -> (34.3545, 85.613, -1.4859)
  line L3863 (34.3545, 85.613, -1.4859) -> (34.4932, 85.4743, -1.4859)
  line L3864 (34.4932, 85.4743, -1.4859) -> (34.6085, 85.3157, -1.4859)
  line L3865 (34.6085, 85.3157, -1.4859) -> (34.6975, 85.1409, -1.4859)
  line L3866 (34.6975, 85.1409, -1.4859) -> (34.7582, 84.9543, -1.4859)
  line L3867 (34.7582, 84.9543, -1.4859) -> (34.7888, 84.7606, -1.4859)
  line L3868 (34.7888, 84.7606, -1.4859) -> (34.7927, 84.6625, -1.4859)
  line L3869 (34.7927, 84.6625, -1.4859) -> (34.7927, 84.1625, -1.4859)
  line L3870 (34.7927, 84.1625, -1.4859) -> (34.7888, 84.0645, -1.4859)
  line L3871 (34.7888, 84.0645, -1.4859) -> (34.7582, 83.8707, -1.4859)
  line L3872 (34.7582, 83.8707, -1.4859) -> (34.6975, 83.6842, -1.4859)
  line L3873 (34.6975, 83.6842, -1.4859) -> (34.6085, 83.5094, -1.4859)
  line L3874 (34.6085, 83.5094, -1.4859) -> (34.4932, 83.3507, -1.4859)
  line L3875 (34.4932, 83.3507, -1.4859) -> (34.3545, 83.212, -1.4859)
  line L3876 (34.3545, 83.212, -1.4859) -> (34.1958, 83.0967, -1.4859)
  line L3877 (34.1958, 83.0967, -1.4859) -> (34.021, 83.0077, -1.4859)
  line L3878 (34.021, 83.0077, -1.4859) -> (33.8345, 82.9471, -1.4859)
  line L3879 (33.8345, 82.9471, -1.4859) -> (33.6408, 82.9164, -1.4859)
  line L3880 (33.6408, 82.9164, -1.4859) -> (33.4446, 82.9164, -1.4859)
  line L3881 (33.4446, 82.9164, -1.4859) -> (33.2509, 82.9471, -1.4859)
  line L3882 (33.2509, 82.9471, -1.4859) -> (33.0643, 83.0077, -1.4859)
  line L3883 (33.0643, 83.0077, -1.4859) -> (32.8896, 83.0967, -1.4859)
  line L3884 (32.8896, 83.0967, -1.4859) -> (32.7309, 83.212, -1.4859)
  line L3885 (32.7309, 83.212, -1.4859) -> (32.5922, 83.3507, -1.4859)
  line L3886 (32.5922, 83.3507, -1.4859) -> (32.4769, 83.5094, -1.4859)
  line L3887 (32.4769, 83.5094, -1.4859) -> (32.3878, 83.6842, -1.4859)
  line L3888 (32.3878, 83.6842, -1.4859) -> (32.3272, 83.8707, -1.4859)
  line L3889 (32.3272, 83.8707, -1.4859) -> (32.2965, 84.0645, -1.4859)
  line L3890 (32.2965, 84.0645, -1.4859) -> (32.2927, 84.1625, -1.4859)
  line L3891 (32.2927, 84.1625, -1.4859) -> (32.2927, 84.6625, -1.4859)
  line L3892 (32.2927, 84.6625, -1.4859) -> (32.2965, 84.7606, -1.4859)
  line L3893 (32.2965, 84.7606, -1.4859) -> (32.3272, 84.9543, -1.4859)
  line L3894 (32.3272, 84.9543, -1.4859) -> (32.3878, 85.1409, -1.4859)
  line L3895 (32.3878, 85.1409, -1.4859) -> (32.4769, 85.3157, -1.4859)
  line L3896 (32.4769, 85.3157, -1.4859) -> (32.5922, 85.4743, -1.4859)
  line L3897 (32.5922, 85.4743, -1.4859) -> (32.7309, 85.613, -1.4859)
  line L3898 (32.7309, 85.613, -1.4859) -> (32.8896, 85.7283, -1.4859)
  line L3899 (32.8896, 85.7283, -1.4859) -> (33.0643, 85.8174, -1.4859)
  line L3900 (33.0643, 85.8174, -1.4859) -> (33.2509, 85.878, -1.4859)
  line L3901 (33.2509, 85.878, -1.4859) -> (33.4446, 85.9087, -1.4859)
  line L3902 (33.4446, 85.9087, -1.4859) -> (33.6408, 85.9087, -1.4859)
  line L3903 (33.6408, 85.9087, -1.4859) -> (33.8345, 85.878, -1.4859)
  line L3904 (68.7595, 85.878, -1.4859) -> (68.946, 85.8174, -1.4859)
  line L3905 (68.946, 85.8174, -1.4859) -> (69.1208, 85.7283, -1.4859)
  line L3906 (69.1208, 85.7283, -1.4859) -> (69.2795, 85.613, -1.4859)
  line L3907 (69.2795, 85.613, -1.4859) -> (69.4182, 85.4743, -1.4859)
  line L3908 (69.4182, 85.4743, -1.4859) -> (69.5335, 85.3157, -1.4859)
  line L3909 (69.5335, 85.3157, -1.4859) -> (69.6225, 85.1409, -1.4859)
  line L3910 (69.6225, 85.1409, -1.4859) -> (69.6832, 84.9543, -1.4859)
  line L3911 (69.6832, 84.9543, -1.4859) -> (69.7138, 84.7606, -1.4859)
  line L3912 (69.7138, 84.7606, -1.4859) -> (69.7177, 84.6625, -1.4859)
  line L3913 (69.7177, 84.6625, -1.4859) -> (69.7177, 84.1625, -1.4859)
  line L3914 (69.7177, 84.1625, -1.4859) -> (69.7138, 84.0645, -1.4859)
  line L3915 (69.7138, 84.0645, -1.4859) -> (69.6832, 83.8707, -1.4859)
  line L3916 (69.6832, 83.8707, -1.4859) -> (69.6225, 83.6842, -1.4859)
  line L3917 (69.6225, 83.6842, -1.4859) -> (69.5335, 83.5094, -1.4859)
  line L3918 (69.5335, 83.5094, -1.4859) -> (69.4182, 83.3507, -1.4859)
  line L3919 (69.4182, 83.3507, -1.4859) -> (69.2795, 83.212, -1.4859)
  line L3920 (69.2795, 83.212, -1.4859) -> (69.1208, 83.0967, -1.4859)
  line L3921 (69.1208, 83.0967, -1.4859) -> (68.946, 83.0077, -1.4859)
  line L3922 (68.946, 83.0077, -1.4859) -> (68.7595, 82.9471, -1.4859)
  line L3923 (68.7595, 82.9471, -1.4859) -> (68.5658, 82.9164, -1.4859)
  line L3924 (68.5658, 82.9164, -1.4859) -> (68.3696, 82.9164, -1.4859)
  line L3925 (68.3696, 82.9164, -1.4859) -> (68.1759, 82.9471, -1.4859)
  line L3926 (68.1759, 82.9471, -1.4859) -> (67.9893, 83.0077, -1.4859)
  line L3927 (67.9893, 83.0077, -1.4859) -> (67.8146, 83.0967, -1.4859)
  line L3928 (67.8146, 83.0967, -1.4859) -> (67.6559, 83.212, -1.4859)
  line L3929 (67.6559, 83.212, -1.4859) -> (67.5172, 83.3507, -1.4859)
  line L3930 (67.5172, 83.3507, -1.4859) -> (67.4019, 83.5094, -1.4859)
  line L3931 (67.4019, 83.5094, -1.4859) -> (67.3128, 83.6842, -1.4859)
  line L3932 (67.3128, 83.6842, -1.4859) -> (67.2522, 83.8707, -1.4859)
  line L3933 (67.2522, 83.8707, -1.4859) -> (67.2215, 84.0645, -1.4859)
  line L3934 (67.2215, 84.0645, -1.4859) -> (67.2177, 84.1625, -1.4859)
  line L3935 (67.2177, 84.1625, -1.4859) -> (67.2177, 84.6625, -1.4859)
  line L3936 (67.2177, 84.6625, -1.4859) -> (67.2215, 84.7606, -1.4859)
  line L3937 (67.2215, 84.7606, -1.4859) -> (67.2522, 84.9543, -1.4859)
  line L3938 (67.2522, 84.9543, -1.4859) -> (67.3128, 85.1409, -1.4859)
  line L3939 (67.3128, 85.1409, -1.4859) -> (67.4019, 85.3157, -1.4859)
  line L3940 (67.4019, 85.3157, -1.4859) -> (67.5172, 85.4743, -1.4859)
  line L3941 (67.5172, 85.4743, -1.4859) -> (67.6559, 85.613, -1.4859)
  line L3942 (67.6559, 85.613, -1.4859) -> (67.8146, 85.7283, -1.4859)
  line L3943 (67.8146, 85.7283, -1.4859) -> (67.9893, 85.8174, -1.4859)
  line L3944 (67.9893, 85.8174, -1.4859) -> (68.1759, 85.878, -1.4859)
  line L3945 (68.1759, 85.878, -1.4859) -> (68.3696, 85.9087, -1.4859)
  line L3946 (68.3696, 85.9087, -1.4859) -> (68.5658, 85.9087, -1.4859)
  line L3947 (68.5658, 85.9087, -1.4859) -> (68.7595, 85.878, -1.4859)
  line L3948 (103.6845, 85.878, -1.4859) -> (103.871, 85.8174, -1.4859)
  line L3949 (103.871, 85.8174, -1.4859) -> (104.0458, 85.7283, -1.4859)
  line L3950 (104.0458, 85.7283, -1.4859) -> (104.2045, 85.613, -1.4859)
  line L3951 (104.2045, 85.613, -1.4859) -> (104.3432, 85.4743, -1.4859)
  line L3952 (104.3432, 85.4743, -1.4859) -> (104.4585, 85.3157, -1.4859)
  line L3953 (104.4585, 85.3157, -1.4859) -> (104.5475, 85.1409, -1.4859)
  line L3954 (104.5475, 85.1409, -1.4859) -> (104.6082, 84.9543, -1.4859)
  line L3955 (104.6082, 84.9543, -1.4859) -> (104.6388, 84.7606, -1.4859)
  line L3956 (104.6388, 84.7606, -1.4859) -> (104.6427, 84.6625, -1.4859)
  line L3957 (104.6427, 84.6625, -1.4859) -> (104.6427, 84.1625, -1.4859)
  line L3958 (104.6427, 84.1625, -1.4859) -> (104.6388, 84.0645, -1.4859)
  line L3959 (104.6388, 84.0645, -1.4859) -> (104.6082, 83.8707, -1.4859)
  line L3960 (104.6082, 83.8707, -1.4859) -> (104.5475, 83.6842, -1.4859)
  line L3961 (104.5475, 83.6842, -1.4859) -> (104.4585, 83.5094, -1.4859)
  line L3962 (104.4585, 83.5094, -1.4859) -> (104.3432, 83.3507, -1.4859)
  line L3963 (104.3432, 83.3507, -1.4859) -> (104.2045, 83.212, -1.4859)
  line L3964 (104.2045, 83.212, -1.4859) -> (104.0458, 83.0967, -1.4859)
  line L3965 (104.0458, 83.0967, -1.4859) -> (103.871, 83.0077, -1.4859)
  line L3966 (103.871, 83.0077, -1.4859) -> (103.6845, 82.9471, -1.4859)
  line L3967 (103.6845, 82.9471, -1.4859) -> (103.4908, 82.9164, -1.4859)
  line L3968 (103.4908, 82.9164, -1.4859) -> (103.2946, 82.9164, -1.4859)
  line L3969 (103.2946, 82.9164, -1.4859) -> (103.1009, 82.9471, -1.4859)
  line L3970 (103.1009, 82.9471, -1.4859) -> (102.9143, 83.0077, -1.4859)
  line L3971 (102.9143, 83.0077, -1.4859) -> (102.7396, 83.0967, -1.4859)
  line L3972 (102.7396, 83.0967, -1.4859) -> (102.5809, 83.212, -1.4859)
  line L3973 (102.5809, 83.212, -1.4859) -> (102.4422, 83.3507, -1.4859)
  line L3974 (102.4422, 83.3507, -1.4859) -> (102.3269, 83.5094, -1.4859)
  line L3975 (102.3269, 83.5094, -1.4859) -> (102.2378, 83.6842, -1.4859)
  line L3976 (102.2378, 83.6842, -1.4859) -> (102.1772, 83.8707, -1.4859)
  line L3977 (102.1772, 83.8707, -1.4859) -> (102.1465, 84.0645, -1.4859)
  line L3978 (102.1465, 84.0645, -1.4859) -> (102.1427, 84.1625, -1.4859)
  line L3979 (102.1427, 84.1625, -1.4859) -> (102.1427, 84.6625, -1.4859)
  line L3980 (102.1427, 84.6625, -1.4859) -> (102.1465, 84.7606, -1.4859)
  line L3981 (102.1465, 84.7606, -1.4859) -> (102.1772, 84.9543, -1.4859)
  line L3982 (102.1772, 84.9543, -1.4859) -> (102.2378, 85.1409, -1.4859)
  line L3983 (102.2378, 85.1409, -1.4859) -> (102.3269, 85.3157, -1.4859)
  line L3984 (102.3269, 85.3157, -1.4859) -> (102.4422, 85.4743, -1.4859)
  line L3985 (102.4422, 85.4743, -1.4859) -> (102.5809, 85.613, -1.4859)
  line L3986 (102.5809, 85.613, -1.4859) -> (102.7396, 85.7283, -1.4859)
  line L3987 (102.7396, 85.7283, -1.4859) -> (102.9143, 85.8174, -1.4859)
  line L3988 (102.9143, 85.8174, -1.4859) -> (103.1009, 85.878, -1.4859)
  line L3989 (103.1009, 85.878, -1.4859) -> (103.2946, 85.9087, -1.4859)
  line L3990 (103.2946, 85.9087, -1.4859) -> (103.4908, 85.9087, -1.4859)
  line L3991 (103.4908, 85.9087, -1.4859) -> (103.6845, 85.878, -1.4859)
  line L3992 (138.6095, 85.878, -1.4859) -> (138.796, 85.8174, -1.4859)
  line L3993 (138.796, 85.8174, -1.4859) -> (138.9708, 85.7283, -1.4859)
  line L3994 (138.9708, 85.7283, -1.4859) -> (139.1295, 85.613, -1.4859)
  line L3995 (139.1295, 85.613, -1.4859) -> (139.2682, 85.4743, -1.4859)
  line L3996 (139.2682, 85.4743, -1.4859) -> (139.3835, 85.3157, -1.4859)
  line L3997 (139.3835, 85.3157, -1.4859) -> (139.4725, 85.1409, -1.4859)
  line L3998 (139.4725, 85.1409, -1.4859) -> (139.5332, 84.9543, -1.4859)
  line L3999 (139.5332, 84.9543, -1.4859) -> (139.5638, 84.7606, -1.4859)
  line L4000 (139.5638, 84.7606, -1.4859) -> (139.5677, 84.6625, -1.4859)
  line L4001 (139.5677, 84.6625, -1.4859) -> (139.5677, 84.1625, -1.4859)
  line L4002 (139.5677, 84.1625, -1.4859) -> (139.5638, 84.0645, -1.4859)
  line L4003 (139.5638, 84.0645, -1.4859) -> (139.5332, 83.8707, -1.4859)
  line L4004 (139.5332, 83.8707, -1.4859) -> (139.4725, 83.6842, -1.4859)
  line L4005 (139.4725, 83.6842, -1.4859) -> (139.3835, 83.5094, -1.4859)
  line L4006 (139.3835, 83.5094, -1.4859) -> (139.2682, 83.3507, -1.4859)
  line L4007 (139.2682, 83.3507, -1.4859) -> (139.1295, 83.212, -1.4859)
  line L4008 (139.1295, 83.212, -1.4859) -> (138.9708, 83.0967, -1.4859)
  line L4009 (138.9708, 83.0967, -1.4859) -> (138.796, 83.0077, -1.4859)
  line L4010 (138.796, 83.0077, -1.4859) -> (138.6095, 82.9471, -1.4859)
  line L4011 (138.6095, 82.9471, -1.4859) -> (138.4158, 82.9164, -1.4859)
  line L4012 (138.4158, 82.9164, -1.4859) -> (138.2196, 82.9164, -1.4859)
  line L4013 (138.2196, 82.9164, -1.4859) -> (138.0259, 82.9471, -1.4859)
  line L4014 (138.0259, 82.9471, -1.4859) -> (137.8393, 83.0077, -1.4859)
  line L4015 (137.8393, 83.0077, -1.4859) -> (137.6646, 83.0967, -1.4859)
  line L4016 (137.6646, 83.0967, -1.4859) -> (137.5059, 83.212, -1.4859)
  line L4017 (137.5059, 83.212, -1.4859) -> (137.3672, 83.3507, -1.4859)
  line L4018 (137.3672, 83.3507, -1.4859) -> (137.2519, 83.5094, -1.4859)
  line L4019 (137.2519, 83.5094, -1.4859) -> (137.1628, 83.6842, -1.4859)
  line L4020 (137.1628, 83.6842, -1.4859) -> (137.1022, 83.8707, -1.4859)
  line L4021 (137.1022, 83.8707, -1.4859) -> (137.0715, 84.0645, -1.4859)
  line L4022 (137.0715, 84.0645, -1.4859) -> (137.0677, 84.1625, -1.4859)
  line L4023 (137.0677, 84.1625, -1.4859) -> (137.0677, 84.6625, -1.4859)
  line L4024 (137.0677, 84.6625, -1.4859) -> (137.0715, 84.7606, -1.4859)
  line L4025 (137.0715, 84.7606, -1.4859) -> (137.1022, 84.9543, -1.4859)
  line L4026 (137.1022, 84.9543, -1.4859) -> (137.1628, 85.1409, -1.4859)
  line L4027 (137.1628, 85.1409, -1.4859) -> (137.2519, 85.3157, -1.4859)
  line L4028 (137.2519, 85.3157, -1.4859) -> (137.3672, 85.4743, -1.4859)
  line L4029 (137.3672, 85.4743, -1.4859) -> (137.5059, 85.613, -1.4859)
  line L4030 (137.5059, 85.613, -1.4859) -> (137.6646, 85.7283, -1.4859)
  line L4031 (137.6646, 85.7283, -1.4859) -> (137.8393, 85.8174, -1.4859)
  line L4032 (137.8393, 85.8174, -1.4859) -> (138.0259, 85.878, -1.4859)
  line L4033 (138.0259, 85.878, -1.4859) -> (138.2196, 85.9087, -1.4859)
  line L4034 (138.2196, 85.9087, -1.4859) -> (138.4158, 85.9087, -1.4859)
  line L4035 (138.4158, 85.9087, -1.4859) -> (138.6095, 85.878, -1.4859)
  line L4036 (24.7274, 89.0483, -1.4859) -> (22.2774, 89.0483, -1.4859)
  line L4037 (22.2774, 89.0483, -1.4859) -> (22.2774, 92.0483, -1.4859)
  line L4038 (22.2774, 92.0483, -1.4859) -> (24.7274, 92.0483, -1.4859)
  line L4039 (24.7274, 92.0483, -1.4859) -> (24.7274, 89.0483, -1.4859)
  line L4040 (59.6524, 89.0483, -1.4859) -> (57.2024, 89.0483, -1.4859)
  line L4041 (57.2024, 89.0483, -1.4859) -> (57.2024, 92.0483, -1.4859)
  line L4042 (57.2024, 92.0483, -1.4859) -> (59.6524, 92.0483, -1.4859)
  line L4043 (59.6524, 92.0483, -1.4859) -> (59.6524, 89.0483, -1.4859)